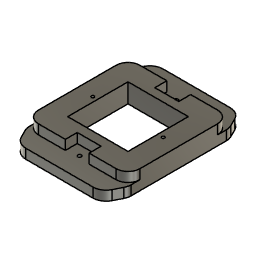
dining-room-cover-v2 (Autodesk Fusion 360 design; units mm, degrees)
Autodesk Fusion 360 part; units mm, degrees
sketch "Sketch1" plane through (0, 0, 0) normal (0, 0, 1) x (1, 0, 0)
  line L0 (-35, -57.5) -> (35, -57.5)
  line L1 (35, -57.5) -> (35, 57.5)
  line L2 (35, 57.5) -> (-35, 57.5)
  line L3 (-35, 57.5) -> (-35, -57.5)
  circle A0 centre (0, -40.5) radius 2.5
  circle A1 centre (0, 40.5) radius 2.5
  dimension "d3" = 70
  dimension "d4" = 115
  dimension "d7" = 5
  dimension "d8" = 5
  constraint horizontal L0
  constraint vertical L1
  constraint horizontal L2
  constraint vertical L3
  measures "d3" distance of L0.start L0.end
  measures "d4" distance of L0.start L2.end
  measures "d7" diameter of A0
  measures "d8" diameter of A1
ref_plane "WorkPlane1" through (0, 0, 6) normal (0, 0, 1) x (1, 0, 0)
sketch "Sketch2" plane through (0, 0, 6) normal (0, 0, 1) x (1, 0, 0)
  line L0 (42.5, -42.5) -> (-42.5, -42.5)
  line L1 (-42.5, -42.5) -> (-42.5, 42.5)
  line L2 (-42.5, 42.5) -> (42.5, 42.5)
  line L3 (42.5, 42.5) -> (42.5, -42.5)
  line L4 (-25.5, 25.5) -> (25, 25.5)
  line L5 (25, 25.5) -> (25, -25)
  line L6 (25, -25) -> (-25.5, -25)
  line L7 (-25.5, -25) -> (-25.5, 25.5)
  circle A0 centre (29.5, 0) radius 0.5
  circle A1 centre (-29.5, 0) radius 0.5
  line L8 (0, -42.5) -> (-5, -42.5)
  line L9 (0, -42.5) -> (0, -32.5)
  line L10 (0, -32.5) -> (-10, -32.5)
  line L11 (-10, -32.5) -> (9.9369, -32.5)
  line L12 (9.9369, -32.5) -> (9.9369, -42.5)
  line L13 (9.9369, -42.5) -> (-10, -42.5)
  line L14 (-10, -42.5) -> (-10, -32.5)
  line L15 (0, 42.5) -> (0, 32.5)
  line L16 (0, 32.5) -> (-10, 32.5)
  line L17 (-10, 32.5) -> (10, 32.5)
  line L18 (10, 32.5) -> (10, 42.5)
  line L19 (-10, 42.5) -> (-10, 32.5)
  line L20 (-26.7, 26.7) -> (26.2, 26.7)
  line L21 (26.2, 26.7) -> (26.2, -26.2)
  line L22 (26.2, -26.2) -> (-26.7, -26.2)
  line L23 (-26.7, -26.2) -> (-26.7, 26.7)
  dimension "d14" = 85
  dimension "d15" = 85
  dimension "d24" = 1
  dimension "d26" = 1
  dimension "d67" = 10
  dimension "d68" = 10
  dimension "d81" = -1.2
  constraint horizontal L0
  constraint vertical L1
  constraint horizontal L2
  constraint vertical L3
  constraint horizontal L4
  constraint vertical L5
  constraint horizontal L6
  constraint vertical L7
  constraint midpoint L0 L8.start
  constraint coincident L0 L8.end
  constraint perpendicular L8 L9
  constraint perpendicular L9 L10
  constraint horizontal L11
  constraint vertical L12
  constraint horizontal L13
  constraint vertical L14
  constraint coincident L0 L12.end
  constraint midpoint L2 L15.start
  constraint perpendicular L2 L15
  constraint perpendicular L15 L16
  constraint horizontal L17
  constraint vertical L18
  constraint vertical L19
  constraint coincident L2 L18.end
  constraint coincident L2 L19.start
  measures "d14" distance of L0.start L0.end
  measures "d15" distance of L0.start L2.end
  measures "d24" diameter of A0
  measures "d26" diameter of A1
  measures "d67" distance of L15.start L15.end
  measures "d68" distance of L15.end L16.end
extrude "Extrude3" add sketch "Sketch1" along normal blind 3 makes body 1
extrude "Extrude4" add sketch "Sketch2" against normal blind 6 contours L0 L1 L2 L3 L10 L11 L12 L14 L16 L17 L18 L19 | L0 L9 L11 L12 L13 | L0 L8 L9 L10 L11 L13 L14 | L2 L15 L17 L18 | L2 L15 L16 L17 L19 | L20 L21 L22 L23 bodies 1
extrude "Extrude5" cut sketch "Sketch2" against normal blind 3 contours L0 L1 L2 L3 L10 L11 L12 L14 L16 L17 L18 L19 | L0 L9 L11 L12 L13 | L0 L8 L9 L10 L11 L13 L14 | L2 L15 L17 L18 | L2 L15 L16 L17 L19 | L20 L21 L22 L23 bodies 1
hole "Hole1" at (0, 40.5, 3) direction (0, 0, -1) diameter 6 depth 12 tip angle 118 bodies 1
hole "Hole2" at (0, -40.5, 3) direction (0, 0, -1) diameter 6 depth 30 tip angle 118 bodies 1
extrude "Extrude6" cut sketch "Sketch2" against normal blind 16 contours A1 bodies 1
extrude "Extrude7" cut sketch "Sketch2" against normal blind 22 contours A0 bodies 1
sketch "Sketch3" plane through (0, 0, 3) normal (0, 0, 1) x (-1, 0, 0)
  circle A0 centre (-29.5, 0) radius 0.5
  circle A1 centre (29.5, 0) radius 0.5
  circle A2 centre (0, 40.5) radius 3
  circle A3 centre (0, -40.5) radius 3
  line L0 (35, 42.5) -> (35, 57.5)
  line L1 (35, 57.5) -> (-35, 57.5)
  line L2 (-35, 57.5) -> (-35, 42.5)
  line L3 (-35, 42.5) -> (-42.5, 42.5)
  line L4 (-42.5, 42.5) -> (-42.5, -42.5)
  line L5 (-42.5, -42.5) -> (-35, -42.5)
  line L6 (-35, -42.5) -> (-35, -57.5)
  line L7 (-35, -57.5) -> (35, -57.5)
  line L8 (35, -57.5) -> (35, -42.5)
  line L9 (35, -42.5) -> (42.5, -42.5)
  line L10 (42.5, -42.5) -> (42.5, 42.5)
  line L11 (42.5, 42.5) -> (35, 42.5)
  line L12 (42.5, -42.5) -> (35, -57.5)
  line L13 (-35, -57.5) -> (-42.5, -42.5)
  line L14 (42.5, 42.5) -> (35, 57.5)
  line L15 (-35, 57.5) -> (-42.5, 42.5)
  constraint coincident L9.end L10.start
  constraint coincident L7.end L8.start
  constraint coincident L6.end L7.start
  constraint coincident L4.end L5.start
  constraint coincident L10.end L11.start
  constraint coincident L0.end L1.start
  constraint coincident L1.end L2.start
  constraint coincident L3.end L4.start
extrude "Extrude8" add sketch "Sketch3" against normal blind 3 contours L0 L11 L14 | L2 L3 L15 | L8 L9 L12 | L5 L6 L13 bodies 1
fillet "Fillet1" radius 11 8 edges at (-35, 57.5, 1.5) (-42.5, 42.5, 1.5) (42.5, -42.5, 1.5) (35, 57.5, 1.5) (42.5, 42.5, 1.5) (35, -57.5, 1.5) (-35, -57.5, 1.5) (-42.5, -42.5, 1.5) on bodies 1
extrude "Extrude9" cut sketch "Sketch2" against normal blind 1000 contours L4 L5 L6 L7 bodies 1
sketch "Sketch4" plane through (0, 0, 3) normal (0, 0, 1) x (-1, 0, 0)
  line L0 (-25, -25.5) -> (-25, 25)
  line L1 (-25, 25) -> (25.5, 25)
  line L2 (25.5, 25) -> (25.5, -25.5)
  line L3 (25.5, -25.5) -> (-25, -25.5)
  circle A0 centre (-29.5, 0) radius 0.5
  circle A1 centre (29.5, 0) radius 0.5
  circle A2 centre (0, 40.5) radius 3
  circle A3 centre (0, -40.5) radius 3
  arc A4 (42.5, 39.9033) -> (41.3387, 44.8226) centre (31.5, 39.9033) ccw
  line L4 (41.3387, 44.8226) -> (38.0403, 51.4193)
  arc A5 (38.0403, 51.4193) -> (28.2016, 57.5) centre (28.2016, 46.5) ccw
  line L5 (28.2016, 57.5) -> (-28.2016, 57.5)
  arc A6 (-28.2016, 57.5) -> (-38.0403, 51.4193) centre (-28.2016, 46.5) ccw
  line L6 (-38.0403, 51.4193) -> (-41.3387, 44.8226)
  arc A7 (-41.3387, 44.8226) -> (-42.5, 39.9033) centre (-31.5, 39.9033) ccw
  line L7 (-42.5, 39.9033) -> (-42.5, -39.9033)
  arc A8 (-42.5, -39.9033) -> (-41.3387, -44.8226) centre (-31.5, -39.9033) ccw
  line L8 (-41.3387, -44.8226) -> (-38.0403, -51.4193)
  arc A9 (-38.0403, -51.4193) -> (-28.2016, -57.5) centre (-28.2016, -46.5) ccw
  line L9 (-28.2016, -57.5) -> (28.2016, -57.5)
  arc A10 (28.2016, -57.5) -> (38.0403, -51.4193) centre (28.2016, -46.5) ccw
  line L10 (38.0403, -51.4193) -> (41.3387, -44.8226)
  arc A11 (41.3387, -44.8226) -> (42.5, -39.9033) centre (31.5, -39.9033) ccw
  line L11 (42.5, -39.9033) -> (42.5, 39.9033)
  circle A12 centre (0, -40.5) radius 3
  circle A13 centre (0, 40.5) radius 3
  constraint concentric A3 A12
  constraint concentric A2 A13
extrude "Extrude10" add sketch "Sketch4" along normal blind 3 separate body contours A2 A13 | A3 A12 makes body 2 at (-2.9851, 40.7987, 4) makes body 3 at (-2.9851, -40.2013, 4)
extrude "Extrude11" add 2 faces at (-0.7877, 39.0912, 6) (-0.7877, -41.9088, 6) along direction (0, 0, -1) blind 6 on bodies 2 3 bodies 2 1 3
extrude "Extrude12" cut 2 faces at (-0.7877, 39.0912, 6) (-0.7877, -41.9088, 6) along direction (0, 0, -1) blind 3 on bodies 2 bodies 2
sketch "Sketch5" plane through (0, 0, 0) normal (0, 0, 1) x (1, 0, 0)
  circle A0 centre (0, 40.5) radius 1.5
  circle A1 centre (0, -40.5) radius 1.5
  point P0 (0, 40.5)
  point P1 (0, -40.5)
  dimension "d55" = 3
  dimension "d56" = 3
  constraint coincident P0 A0.centre
  constraint coincident P1 A1.centre
  measures "d55" diameter of A0
  measures "d56" diameter of A1
hole "Hole3" at (0.0235, 40.4861, 3) direction (0, 0, -1) diameter 3 depth 30 tip angle 118 bodies 2
hole "Hole4" at (-0.0048, -40.5021, 3) direction (0, 0, -1) diameter 3 depth 12 tip angle 118 bodies 2
extrude "Extrude13" add sketch "Sketch2" against normal blind 3 contours L0 L1 L2 L3 L10 L11 L12 L14 L16 L17 L18 L19 | L0 L9 L11 L12 L13 | L0 L8 L9 L10 L11 L13 L14 | L2 L15 L17 L18 | L2 L15 L16 L17 L19 | L20 L21 L22 L23 bodies 2
fillet "Fillet2" radius 10 4 edges at (-42.5, 42.5, 4.5) (42.5, 42.5, 4.5) (42.5, -42.5, 4.5) (-42.5, -42.5, 4.5) on bodies 2
extrude "Extrude14" cut sketch "Sketch2" against normal blind 3 contours L0 L9 L11 L12 L13 | L0 L8 L9 L10 L11 L13 L14 | L2 L15 L17 L18 | L2 L15 L16 L17 L19 bodies 2
extrude "Extrude15" add 1 faces at (-18.4016, -41.0245, 0) along direction (0, 0, -1) blind 5 on bodies 2 bodies 2
extrude "Extrude16" add 1 faces at (-38.3333, 0, 6) along direction (0, 0, 1) blind 5 on bodies 2 bodies 2
ref_plane "WorkPlane2" through (0, 0, 11) normal (0, 0, 1) x (1, 0, 0)
sketch "Sketch6" plane through (0, 0, 11) normal (0, 0, 1) x (1, 0, 0)
  circle A0 centre (-29.5, 0) radius 1.25
  circle A1 centre (29.5, 0) radius 1.25
  dimension "d77" = 2.5
  dimension "d78" = 2.5
  measures "d77" diameter of A0
  measures "d78" diameter of A1
extrude "Extrude17" cut sketch "Sketch6" against normal blind 52 bodies 2
sketch "Sketch7" plane through (0, 0, 0) normal (0, 0, 1) x (1, 0, 0)
